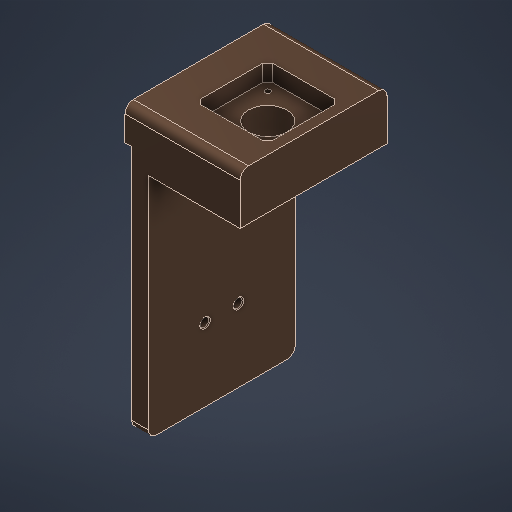
# Autodesk Inventor part: Z Bracket
Saved by Autodesk Inventor 2027.1 (Build 311270010, 270A)
## iProperties
Created: 2026-10-04
Part Number: Z Bracket
Material: PC/ABS Plastic
Document SubType Name: Modeling
Designer: Ahmed
Density: 1.1 g/cm^3
Appearance: Bronze - Satin
Author: Ahmed
Autodesk Inventor part; units mm, degrees
ref_plane "YZ Plane" through (0, 0, 0) normal (1, 0, 0) x (0, 1, 0)
ref_plane "XZ Plane" through (0, 0, 0) normal (0, 1, 0) x (-1, 0, 0)
ref_plane "XY Plane" through (0, 0, 0) normal (0, 0, 1) x (1, 0, 0)
sketch "Sketch1" plane through (0, 0, 0) normal (1, 0, 0) x (0, 1, 0)
  line L0 (-78.5, -44) -> (78.5, -44)
  line L1 (83.5, -39) -> (83.5, 39)
  line L2 (78.5, 44) -> (-78.5, 44)
  line L3 (-83.5, 39) -> (-83.5, -39)
  line L4 (-83.5, -44) -> (83.5, 44) construction
  line L5 (83.5, -44) -> (-83.5, 44) construction
  line L6 (-20, -20) -> (20, -20)
  line L7 (20, -20) -> (20, 20)
  line L8 (20, 20) -> (-20, 20)
  line L9 (-20, 20) -> (-20, -20)
  line L10 (-20, -20) -> (20, 20) construction
  line L11 (20, -20) -> (-20, 20) construction
  circle A0 centre (20, 20) radius 7
  circle A1 centre (20, -20) radius 7
  circle A2 centre (-20, 20) radius 7
  circle A3 centre (-20, -20) radius 7
  arc A4 (83.5, 39) -> (78.5, 44) centre (78.5, 39) ccw
  arc A5 (78.5, -44) -> (83.5, -39) centre (78.5, -39) ccw
  arc A6 (-83.5, -39) -> (-78.5, -44) centre (-78.5, -39) ccw
  arc A7 (-78.5, 44) -> (-83.5, 39) centre (-78.5, 39) ccw
  line L12 (53.5, 44) -> (53.5, -44)
  line L13 (63.5, -44) -> (63.5, 44)
  circle A8 centre (-39.85, -10) radius 2.65
  circle A9 centre (39.85, -10) radius 2.65
  circle A10 centre (-39.85, 10) radius 2.65
  circle A11 centre (39.85, 10) radius 2.65
  point P0 (0, 0)
  dimension "d0" = 167
  dimension "d1" = 88
  dimension "d2" = 40
  dimension "d3" = 40
  dimension "d4" = 14
  dimension "d7" = 40
  dimension "d10" = 40
  dimension "d15" = 5
  dimension "d16" = 30
  dimension "d49" = 20
  dimension "d53" = 5.3
  dimension "d54" = 10
  dimension "d55" = 39.85
  dimension "d58" = 79.7
  dimension "d61" = 20
  constraints: 28 end point, 12 centre point, 12 point on line, 8 point on circle, 8 tangent, 4 horizontal, 4 midpoint, 4 parallel, 4 perpendicular, 3 equal radius, 2 vertical, 1 coincident, 12 other
  measures "d0" distance of L5.end L4.end
  measures "d1" distance of L4.end L5.start
  measures "d2" distance of L8.end L7.end
  measures "d3" distance of L7.end L6.end
  measures "d4" diameter of A0
  measures "d7" distance of A0.centre A1.centre
  measures "d10" distance of A0.centre A2.centre
  measures "d15" radius of A4
  measures "d16" distance between parallel lines of L1 L12
  measures "d49" distance between parallel lines of L13 L1
  measures "d53" diameter of A8
  measures "d54" vertical distance of point (0, 0) A8.centre
  measures "d55" horizontal distance of point (0, 0) A8.centre
  measures "d58" distance of A8.centre A9.centre
  measures "d61" distance of A8.centre A10.centre
extrude "Extrusion1" add sketch "Sketch1" along normal blind 10 contours A6 L3 A7 L2 L12 L0 | L12 L2 L13 L0 | L13 L2 A4 L1 A5 L0 | L9 A3 L6 | L6 A3 L9 | A3 L9 A2 L8 A0 L7 A1 L6 | A1 L7 L6 | L6 L7 A1 | A2 L8 L9 | L9 L8 A2 | A0 L8 L7 | L7 L8 A0 | A8 | A9 | A10 | A11
extrude "Extrusion2" add sketch "Sketch1" along normal blind 55 from surface at 10 contours L12 L2 L13 L0 | L13 L2 A4 L1 A5 L0
extrude "Extrusion3" cut sketch "Sketch1" along normal blind 3 contours L9 A3 L6 | L6 A3 L9 | A1 L7 L6 | L6 L7 A1 | A2 L8 L9 | L9 L8 A2 | A0 L8 L7 | L7 L8 A0
fillet "Fillet1" radius 1 4 edges at (0, 13, -20) (0, 13, 20) (0, -27, 20) (0, -27, -20)
sketch "Sketch2" plane through (65, 83.5, 39) normal (0, 1, 0) x (1, 0, 0)
  line L0 (-55, 83) -> (-55, -5) projected
  line L1 (-55, 39) -> (0, 39)
  line L2 (0, 83) -> (0, -5) projected
  line L3 (-9, 60.5) -> (-46, 60.5)
  line L4 (-49, 57.5) -> (-49, 20.5)
  line L5 (-46, 17.5) -> (-9, 17.5)
  line L6 (-6, 20.5) -> (-6, 57.5)
  line L7 (-6, 60.5) -> (-49, 17.5) construction
  line L8 (-49, 60.5) -> (-6, 17.5) construction
  line L9 (-43, 23.5) -> (-12, 23.5)
  line L10 (-12, 23.5) -> (-12, 54.5)
  line L11 (-12, 54.5) -> (-43, 54.5)
  line L12 (-43, 54.5) -> (-43, 23.5)
  line L13 (-43, 23.5) -> (-12, 54.5) construction
  line L14 (-12, 23.5) -> (-43, 54.5) construction
  circle A0 centre (-43, 23.5) radius 1.65
  circle A1 centre (-43, 54.5) radius 1.65
  circle A2 centre (-12, 23.5) radius 1.65
  circle A3 centre (-12, 54.5) radius 1.65
  line L15 (-49, 20.5) -> (-46, 17.5)
  line L16 (-49, 57.5) -> (-46, 60.5)
  line L17 (-9, 60.5) -> (-6, 57.5)
  line L18 (-6, 20.5) -> (-9, 17.5)
  circle A4 centre (-27.5, 39) radius 11.5
  point P0 (-65, 39)
  dimension "d24" = 43
  dimension "d25" = 43
  dimension "d26" = 31
  dimension "d27" = 31
  dimension "d28" = 3.3
  dimension "d31" = 31
  dimension "d34" = 31
  dimension "d37" = 3
  dimension "d38" = 3
  dimension "d39" = 3
  dimension "d40" = 3
  dimension "d41" = 3
  dimension "d42" = 3
  dimension "d43" = 3
  dimension "d44" = 3
  dimension "d52" = 23
  constraints: 34 end point, 8 point on line, 7 midpoint, 5 centre point, 4 parallel, 3 horizontal, 2 coincident, 2 perpendicular, 1 vertical, 6 other
  measures "d24" distance of L8.end L7.end
  measures "d25" distance of L7.end L8.start
  measures "d26" distance of L11.end L10.end
  measures "d27" distance of L10.end L9.end
  measures "d28" diameter of A0
  measures "d31" distance of A0.centre A1.centre
  measures "d34" distance of A0.centre A2.centre
  measures "d37" distance of L4.end L7.end
  measures "d38" distance of L5.start L7.end
  measures "d39" distance of L4.start L8.start
  measures "d40" distance of L3.end L8.start
  measures "d41" distance of L3.start L7.start
  measures "d42" distance of L6.end L7.start
  measures "d43" distance of L6.start L8.end
  measures "d44" distance of L5.end L8.end
  measures "d52" diameter of A4
extrude "Extrusion5" cut sketch "Sketch2" against normal through all contours A4 L1 | L1 A4 | A1 L11 L12 | L12 L11 A1 | A0 L9 L12 | L12 L9 A0 | A3 L10 L11 | L11 L10 A3 | A2 L10 L9 | L9 L10 A2
extrude "Extrusion6" cut sketch "Sketch2" against normal blind 10
extrude "Extrusion7" add sketch "Sketch1" against normal blind 4 contours L13 L2 A4 L1 A5 L0
extrude "Extrusion8" cut sketch "Sketch1" along normal through all contours A8 | A9 | A10 | A11
chamfer "Chamfer1" distance 0.5 angle 45 8 edges at (10, 37.2, 10) (10, 37.2, -10) (10, -42.5, 10) (10, -42.5, -10) (20.35, 53.5, 15.5) (51.35, 53.5, 15.5) (51.35, 53.5, -15.5) (20.35, 53.5, -15.5)
equation "\"d58\" = 2 * d55"
equation "\"d61\" = 2 * d54"
equation "\"d31\" = d26"
equation "\"d34\" = d26"
equation "\"d38\" = d37"
equation "\"d39\" = d37"
equation "\"d40\" = d39"
equation "\"d41\" = d37"
equation "\"d42\" = d41"
equation "\"d43\" = d37"
equation "\"d44\" = d43"
body "Solid1"
